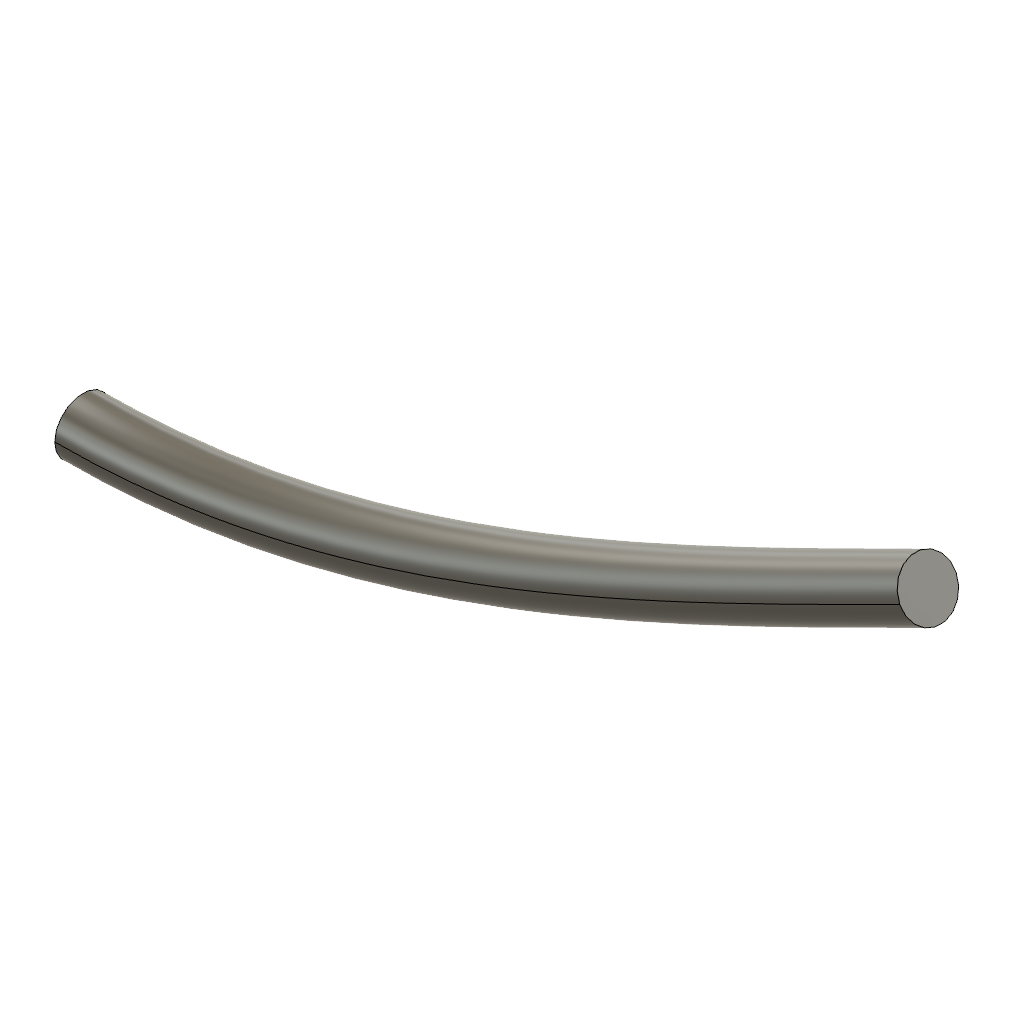
polynomial_cubic (Autodesk Fusion 360 design; units mm, degrees)
part number: 2026-10-21-16-32-30-514
Autodesk Fusion 360 part; units mm, degrees
sketch "OwnedNurbsSweepPath_polynomial_cubic" plane through (0, 0, 0) normal (0, 0, 1) x (1, 0, 0)
  spline S0 degree 3 poles (0, 0) (20, 0) (40, 10) (60, 20) knots 0 0 0 0 1 1 1 1
sketch "OwnedNurbsSweepCircle_polynomial_cubic" plane through (0, 0, 0) normal (1, 0, 0) x (0, 0, -1)
  circle A0 centre (0, 0) radius 2
sweep "OwnedFixedNurbsSweep_polynomial_cubic" add profiles "OwnedNurbsSweepCircle_polynomial_cubic" path "OwnedNurbsSweepPath_polynomial_cubic" along S0 section 1
